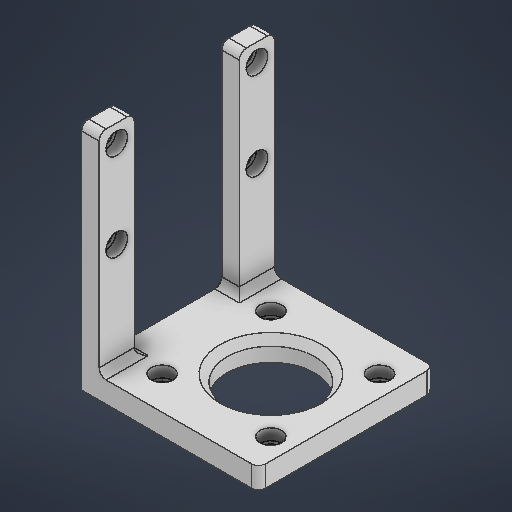
# Autodesk Inventor part: weight gasket
Saved by Autodesk Inventor 2026.2 (Build 302298010, 298A)
## iProperties
Created: 2026-05-03
Part Number: weight gasket
Material: 일반
Document SubType Name: Modeling
Designer: work
Density: 1 g/cm^3
Appearance: 기본값
Author: work
Autodesk Inventor part; units mm, degrees
ref_plane "YZ Plane" through (0, 0, 0) normal (1, 0, 0) x (0, 1, 0)
ref_plane "XZ Plane" through (0, 0, 0) normal (0, 1, 0) x (-1, 0, 0)
ref_plane "XY Plane" through (0, 0, 0) normal (0, 0, 1) x (1, 0, 0)
sketch "스케치1" plane through (0, 0, 0) normal (1, 0, 0) x (0, 1, 0)
  line L0 (-12.5, 20) -> (12.5, 20) construction
  line L1 (12.5, 20) -> (12.5, -20) construction
  line L2 (12.5, -20) -> (-12.5, -20) construction
  line L3 (-12.5, -20) -> (-12.5, 20) construction
  line L4 (-12.5, 20) -> (12.5, -20) construction
  line L5 (12.5, 20) -> (-12.5, -20) construction
  circle A0 centre (12.5, 20) radius 2
  circle A1 centre (-12.5, 20) radius 2
  circle A2 centre (-12.5, -20) radius 2
  circle A3 centre (12.5, -20) radius 2
  line L6 (17.5, 25) -> (-48.5, 25)
  line L7 (-48.5, 25) -> (-48.5, -25)
  line L8 (-48.5, -25) -> (17.5, -25)
  line L9 (17.5, -25) -> (17.5, 25)
  line L10 (17.5, -15) -> (-42.5, -15)
  line L11 (-42.5, -15) -> (-42.5, 15)
  line L12 (-42.5, 15) -> (17.5, 15)
  line L13 (17.5, 15) -> (17.5, -15)
  point P0 (0, 0)
  point P1 (17.5, 0)
  point P2 (17.5, 15)
  dimension "d0" = 25
  dimension "d1" = 40
  dimension "d2" = 4
  dimension "d3" = 4
  dimension "d4" = 4
  dimension "d5" = 4
  dimension "d6" = 5
  dimension "d7" = 5
  dimension "d8" = 5
  dimension "d9" = 5
  dimension "d10" = 6
  dimension "d11" = 30
  constraints: 28 end point, 6 parallel, 4 centre point, 4 coincident, 4 midpoint, 3 horizontal, 3 perpendicular
  measures "d0" distance of L1.end L2.end
  measures "d1" distance of L0.end L1.end
  measures "d2" diameter of A0
  measures "d3" diameter of A1
  measures "d4" diameter of A2
  measures "d5" diameter of A3
  measures "d6" distance between parallel lines of L8 L2
  measures "d7" distance between parallel lines of L9 L1
  measures "d8" distance between parallel lines of L6 L0
  measures "d9" distance between parallel lines of L2 L10
  measures "d10" distance between parallel lines of L7 L11
  measures "d11" distance between parallel lines of L3 L11
extrude "돌출1" add sketch "스케치1" along normal blind 6 contours L9 L12 L11 L10 L8 L7 L6
sketch "스케치2" plane through (0, -42.5, 15) normal (0, 1, 0) x (1, 0, 0)
  line L0 (0, 15) -> (30, 15) construction
  line L1 (0, -10) -> (6, -10) projected
  line L2 (6, -10) -> (51.5, -10)
  line L3 (51.5, -10) -> (51.5, 40)
  line L4 (51.5, 40) -> (6, 40)
  line L5 (6, 40) -> (6, -10)
  line L6 (45.5, -0.5) -> (14.5, -0.5) construction
  line L7 (14.5, -0.5) -> (14.5, 30.5) construction
  line L8 (14.5, 30.5) -> (45.5, 30.5) construction
  line L9 (45.5, 30.5) -> (45.5, -0.5) construction
  line L10 (45.5, -0.5) -> (14.5, 30.5) construction
  line L11 (14.5, -0.5) -> (45.5, 30.5) construction
  circle A0 centre (45.5, -0.5) radius 2
  circle A1 centre (45.5, 30.5) radius 2
  circle A2 centre (14.5, 30.5) radius 2
  circle A3 centre (14.5, -0.5) radius 2
  circle A4 centre (30, 15) radius 12.5
  dimension "d14" = 31
  dimension "d15" = 31
  dimension "d16" = 30
  dimension "d17" = 4
  dimension "d18" = 4
  dimension "d19" = 4
  dimension "d20" = 4
  dimension "d21" = 6
  dimension "d22" = 25
  constraints: 22 end point, 5 centre point, 5 coincident, 4 parallel, 3 horizontal, 2 midpoint, 2 perpendicular, 1 point on line
  measures "d14" distance of L7.end L8.end
  measures "d15" distance of L6.end L7.end
  measures "d16" distance of L0.start L0.end
  measures "d17" diameter of A0
  measures "d18" diameter of A1
  measures "d19" diameter of A2
  measures "d20" diameter of A3
  measures "d21" distance between parallel lines of L3 L9
  measures "d22" diameter of A4
extrude "돌출2" add sketch "스케치2" against normal blind 6
fillet "모깎기1" radius 2 4 edges at (6, -42.5, 20) (3, -42.5, 15) (6, -42.5, -20) (3, -42.5, -15)
sketch "스케치3" plane through (51.5, -42.5, 25) normal (0, 1, 0) x (1, 0, 0)
  circle A0 centre (-37, 40.5) radius 2 projected
  circle A1 centre (-6, 40.5) radius 2 projected
  circle A2 centre (-6, 9.5) radius 2 projected
  circle A3 centre (-37, 9.5) radius 2 projected
  point P0 (-51.5, 25)
  constraints: 4 coincident
hole "구멍1" at (14.5, -42.5, -15.5) at (45.5, -42.5, -15.5) at (45.5, -42.5, 15.5) at (14.5, -42.5, 15.5) direction (0, -1, 0) diameter 4 end through all counterbore diameter 6.2 counterbore depth 3.2
sketch "스케치4" plane through (6, 0, 0) normal (1, 0, 0) x (0, 0, -1)
  circle A0 centre (-20, 12.5) radius 2 projected
  circle A1 centre (-20, -12.5) radius 2 projected
  circle A2 centre (20, -12.5) radius 2 projected
  circle A3 centre (20, 12.5) radius 2 projected
  point P0 (0, 0)
  constraints: 4 coincident
hole "구멍2" at (6, 12.5, 20) at (6, -12.5, 20) at (6, -12.5, -20) at (6, 12.5, -20) direction (-1, 0, 0) diameter 4 end through all counterbore diameter 6.2 counterbore depth 3.2
fillet "모깎기2" radius 2 6 edges at (3, 17.5, 25) (3, 17.5, 15) (3, 17.5, -15) (3, 17.5, -25) (51.5, -45.5, -25) (51.5, -45.5, 25)
chamfer "모따기1" distance 1 angle 45 14 edges at (0, -42.5, 0) (0, -41.9142, 14.4142) (0, -12.5, 15) (0, 16.9142, 15.5858) (0, 17.5, 20) (0, 16.9142, 24.4142) (0, -16.5, 25) (0, -41.9142, -14.4142) (0, -12.5, -15) (0, 16.9142, -15.5858) (0, 17.5, -20) (0, 16.9142, -24.4142) (0, -16.5, -25) (0, -48.5, 0)
chamfer "모따기2" distance 2 angle 45 1 edges at (17.5, -42.5, 0)
